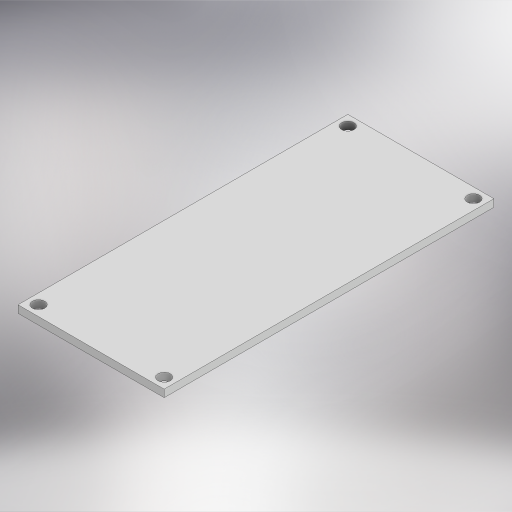
# Autodesk Inventor part: dummy_board
Saved by Autodesk Inventor 2023.5 (Build 275446000, 446)
## iProperties
Created: 2026-10-31
Part Number: dummy_board
Material: Generic
Document SubType Name: Modeling
Designer: WORKPLUS
Density: 1 g/cm^3
Appearance: Default
Author: WORKPLUS
Autodesk Inventor part; units mm, degrees
ref_plane "YZ Plane" through (0, 0, 0) normal (1, 0, 0) x (0, 1, 0)
ref_plane "XZ Plane" through (0, 0, 0) normal (0, 1, 0) x (-1, 0, 0)
ref_plane "XY Plane" through (0, 0, 0) normal (0, 0, 1) x (1, 0, 0)
sketch "Sketch1" plane through (0, 0, 0) normal (0, 1, 0) x (-1, 0, 0)
  line L0 (-25.4, 62.55) -> (25.4, 62.55)
  line L1 (25.4, 62.55) -> (25.4, -62.55)
  line L2 (25.4, -62.55) -> (-25.4, -62.55)
  line L3 (-25.4, -62.55) -> (-25.4, 62.55)
  line L4 (-25.4, 62.55) -> (25.4, -62.55) construction
  line L5 (25.4, 62.55) -> (-25.4, -62.55) construction
  circle A0 centre (25.4, 62.55) radius 2.5
  circle A1 centre (25.4, -62.55) radius 2.5
  circle A2 centre (-25.4, -62.55) radius 2.5
  circle A3 centre (-25.4, 62.55) radius 2.5
  line L6 (29.5515, -66.7015) -> (29.5515, 66.7015)
  line L7 (29.5515, 66.7015) -> (-29.5515, 66.7015)
  line L8 (-29.5515, 66.7015) -> (-29.5515, -66.7015)
  line L9 (-29.5515, -66.7015) -> (29.5515, -66.7015)
  point P0 (0, 0)
  dimension "d0" = 125.1
  dimension "d1" = 50.8
  dimension "d2" = 5
  dimension "d3" = 5
  dimension "d4" = 5
  dimension "d5" = 5
  constraints: 20 end point, 4 centre point, 4 coincident, 4 parallel, 2 midpoint, 2 perpendicular, 1 horizontal, 3 other
  measures "d0" distance of L0.end L1.end
  measures "d1" distance of L1.end L2.end
  measures "d2" diameter of A0
  measures "d3" diameter of A1
  measures "d4" diameter of A2
  measures "d5" diameter of A3
extrude "Extrusion1" add sketch "Sketch1" along normal blind 3 contours L0 A0 L1 A1 L2 A2 L3 A3 | L9 L8 L7 L6
body "Solid1"
